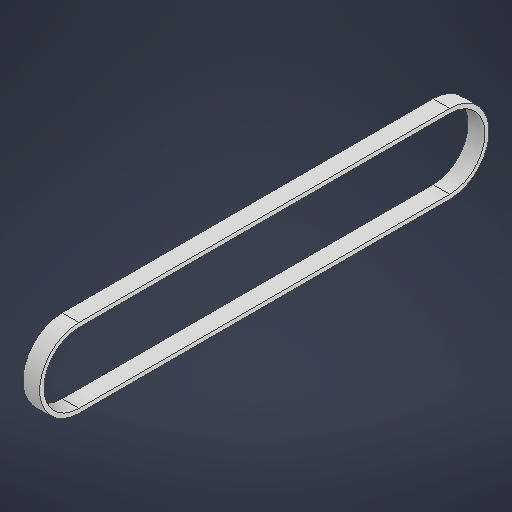
# Autodesk Inventor part: Timing Belt
Saved by Autodesk Inventor 2026.2 (Build 302298010, 298A)
## iProperties
Created: 2026-05-14
Part Number: Timing Belt
Material: Generic
Document SubType Name: Modeling
Designer: User
Density: 1 g/cm^3
Appearance: Default
Author: User
Autodesk Inventor part; units mm, degrees
ref_plane "YZ Plane" through (0, 0, 0) normal (1, 0, 0) x (0, 1, 0)
ref_plane "XZ Plane" through (0, 0, 0) normal (0, 1, 0) x (-1, 0, 0)
ref_plane "XY Plane" through (0, 0, 0) normal (0, 0, 1) x (1, 0, 0)
sketch "Sketch1" plane through (0, 0, 0) normal (1, 0, 0) x (0, 1, 0)
  arc A0 (35, 0) -> (-35, 0) centre (0, 0) ccw
  arc A1 (-35, -330) -> (35, -330) centre (0, -330) ccw
  line L0 (35, 0) -> (35, -330)
  line L1 (-35, 0) -> (-35, -330)
  arc A2 (-31.19, -330) -> (31.19, -330) centre (0, -330) ccw
  arc A3 (31.19, 0) -> (-31.19, 0) centre (0, 0) ccw
  line L2 (31.19, 0) -> (31.19, -330)
  line L3 (-31.19, -330) -> (-31.19, 0)
  dimension "d0" = 70
  dimension "d1" = 70
  dimension "d2" = 330
  dimension "d7" = 3.81
  constraints: 8 end point, 8 point on circle, 4 centre point, 4 tangent, 3 coincident, 1 vertical
  measures "d0" diameter of A0
  measures "d1" diameter of A1
  measures "d2" distance of L0.start L0.end
  measures "d7" distance between parallel lines of L0 L2
extrude "Extrusion1" add sketch "Sketch1" along normal blind 15
body "Solid1"
